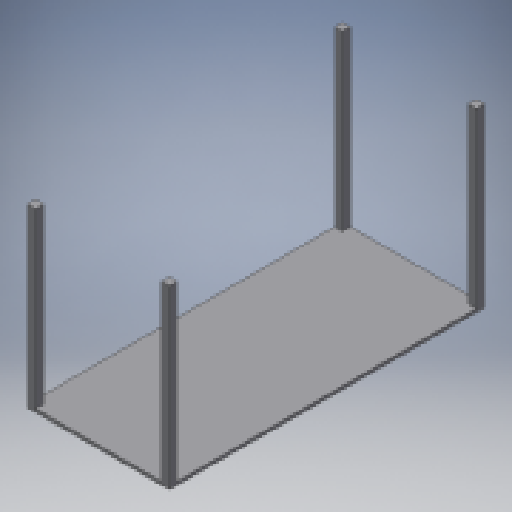
# Autodesk Inventor part: BT015_thutrn22_26
Saved by Autodesk Inventor 2025.3 (Build 293356000, 356)
## iProperties
Company: HTBLA Kaindorf
RuleStatus: InUse
Created: 2026-08-13
Part Number: BT015_thutrn22_26
Project: Biegeroboter
Material: Generisch
Description: Tisch
Document SubType Name: Modeling
Designer: thutrn22
Density: 1 g/cm^3
Appearance: Vorgabe
Mass: 47000 g
Surface Area: 45960 cm^2
Volume: 47000 cm^3
AfterDocNew0: iProperties-Editor_aufrufen
Author: trist
Keywords: 2026
Autodesk Inventor part; units mm, degrees
ref_plane "YZ Plane" through (0, 0, 0) normal (1, 0, 0) x (0, 1, 0)
ref_plane "XZ Plane" through (0, 0, 0) normal (0, 1, 0) x (-1, 0, 0)
ref_plane "XY Plane" through (0, 0, 0) normal (0, 0, 1) x (1, 0, 0)
sketch "Skizze3" plane through (0, 0, 0) normal (0, 0, 1) x (1, 0, 0)
  line L0 (-1400, 0) -> (1400, 0) projected
  line L1 (0, -630) -> (0, 630) projected
  line L2 (-1000, 450) -> (1000, 450)
  line L3 (1000, 450) -> (1000, -450)
  line L4 (1000, -450) -> (-1000, -450)
  line L5 (-1000, -450) -> (-1000, 450)
  point P0 (0, 0)
  dimension "d4" = 900
  dimension "d5" = 2000
  constraints: 8 end point, 2 parallel, 1 horizontal, 1 perpendicular, 2 other
  measures "d4" distance between parallel lines of L4 L2
  measures "d5" distance between parallel lines of L5 L3
extrude "Extrusion3" add sketch "Skizze3" along normal blind 20
sketch "Skizze4" plane through (0, 0, 20) normal (0, 0, 1) x (1, 0, 0)
  line L0 (1000, 450) -> (-1000, 450) projected
  line L1 (-1000, 450) -> (-950, 450)
  line L2 (-950, 450) -> (-950, 400)
  line L3 (-950, 400) -> (-1000, 400)
  line L4 (-1000, 400) -> (-1000, 450)
  line L5 (-1000, 450) -> (-1000, -450) projected
  line L6 (-1000, -450) -> (-950, -450)
  line L7 (-950, -450) -> (-950, -400)
  line L8 (-950, -400) -> (-1000, -400)
  line L9 (-1000, -400) -> (-1000, -450)
  line L10 (1000, 450) -> (950, 450)
  line L11 (950, 450) -> (950, 400)
  line L12 (950, 400) -> (1000, 400)
  line L13 (1000, 400) -> (1000, 450)
  line L14 (-1000, -450) -> (1000, -450) projected
  line L15 (1000, -450) -> (950, -450)
  line L16 (950, -450) -> (950, -400)
  line L17 (950, -400) -> (1000, -400)
  line L18 (1000, -400) -> (1000, -450)
  point P0 (0, 0)
  dimension "d8" = 50
  dimension "d9" = 50
  dimension "d10" = 50
  dimension "d11" = 50
  dimension "d12" = 50
  dimension "d13" = 50
  constraints: 32 end point, 8 parallel, 4 horizontal, 4 perpendicular, 2 point on line
  measures "d8" distance of L2.end L3.end
  measures "d9" distance of L1.end L2.end
  measures "d10" distance of L8.end L7.end
  measures "d11" distance of L7.end L6.end
  measures "d12" distance of L12.end L11.end
  measures "d13" distance of L11.end L10.end
extrude "Extrusion4" add sketch "Skizze4" along normal blind 1100
